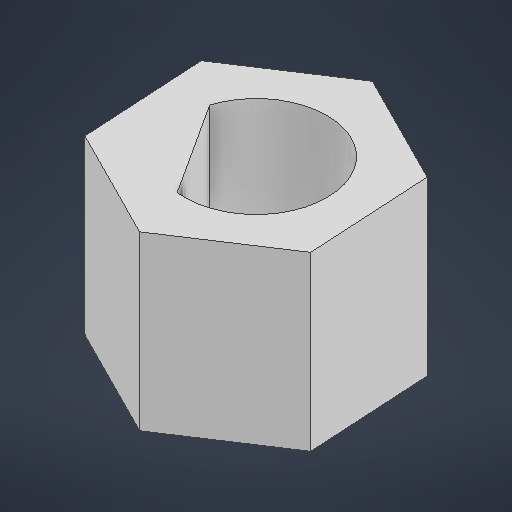
# Autodesk Inventor part: wheeladapter
Saved by Autodesk Inventor 2026.2 (Build 302298000, 298)
## iProperties
Created: 2026-10-13
Part Number: wheeladapter
Material: Generic
Document SubType Name: Modeling
Designer: Brian Wang
Density: 1 g/cm^3
Appearance: Default
Author: Brian Wang
Autodesk Inventor part; units mm, degrees
ref_plane "YZ Plane" through (0, 0, 0) normal (1, 0, 0) x (0, 1, 0)
ref_plane "XZ Plane" through (0, 0, 0) normal (0, 1, 0) x (-1, 0, 0)
ref_plane "XY Plane" through (0, 0, 0) normal (0, 0, 1) x (1, 0, 0)
sketch "Sketch1" plane through (0, 0, 0) normal (0, 1, 0) x (-1, 0, 0)
  line L0 (2.5623, -1.2916) -> (0.1625, -2.8648)
  line L1 (0.1625, -2.8648) -> (-2.3997, -1.5732)
  line L2 (-2.3997, -1.5732) -> (-2.5623, 1.2916)
  line L3 (-2.5623, 1.2916) -> (-0.1625, 2.8648)
  line L4 (-0.1625, 2.8648) -> (2.3997, 1.5732)
  line L5 (2.3997, 1.5732) -> (2.5623, -1.2916)
  circle A0 centre (0, 0) radius 1.65
  line L6 (1.7605, -0.787) -> (-0.197, 2.2362)
  line L7 (-2.1429, 0.2738) -> (-0.2431, -2.6603)
  point P0 (0.1896, 1.6391)
  point P1 (1.5731, -0.4977)
  dimension "d0" = 4.97
  dimension "d5" = 3.3
  dimension "d6" = 2.7
  constraints: 16 end point, 2 coincident, 1 centre point, 1 parallel, 1 point on line, 1 tangent, 13 other
  measures "d0" distance between parallel lines of L2 L5
  measures "d5" diameter of A0
  measures "d6" distance between parallel lines of L7 L6
extrude "Extrusion1" add sketch "Sketch1" along normal blind 4 contours L0 L1 L2 L3 L4 L5 | A0 L6 picked at (1.0969, 0.7468)
body "Solid1"
